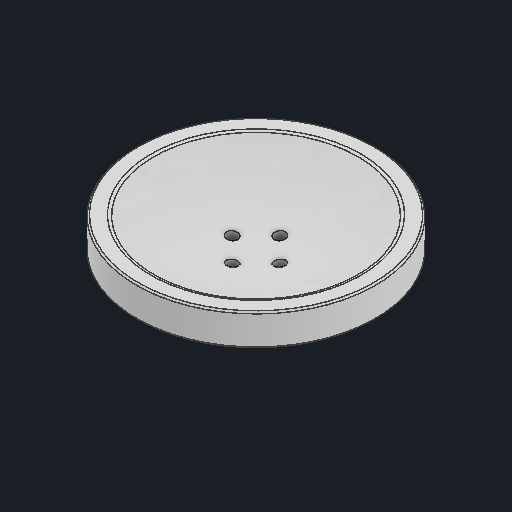
# Autodesk Inventor part: 접시
Saved by Autodesk Inventor 2026.3 (Build 303398000, 398)
## iProperties
Created: 2026-09-11
Part Number: 접시
Material: 일반
Document SubType Name: Modeling
Designer: khw
Density: 1 g/cm^3
Appearance: 기본값
Author: khw
Autodesk Inventor part; units mm, degrees
ref_plane "YZ Plane" through (0, 0, 0) normal (1, 0, 0) x (0, 1, 0)
ref_plane "XZ Plane" through (0, 0, 0) normal (0, 1, 0) x (-1, 0, 0)
ref_plane "XY Plane" through (0, 0, 0) normal (0, 0, 1) x (1, 0, 0)
sketch "스케치1" plane through (0, 0, 0) normal (1, 0, 0) x (0, 1, 0)
  line L0 (0, 0) -> (0, -25)
  line L1 (0, -25) -> (25, -25)
  line L2 (25, -25) -> (25, -75)
  line L3 (25, -75) -> (45, -75)
  arc A0 (25, 0) -> (45, -65) centre (140.625, 0) ccw
  line L4 (25, 0) -> (0, 0)
  line L5 (45, -75) -> (45, -65)
  point P0 (0, -12.5)
  dimension "d0" = 50
  dimension "d1" = 150
  dimension "d2" = 20
  dimension "d3" = 25
  dimension "d4" = 10
  dimension "d5" = 20
  constraints: 12 end point, 4 perpendicular, 2 point on circle, 1 centre point, 1 horizontal, 1 line through centre, 1 midpoint, 1 vertical
  measures "d0" diameter of L1 L4
  measures "d1" diameter of L3 L4
  measures "d2" distance of L3.end L2.end
  measures "d3" distance from line of point (0, -12.5) L2
  measures "d4" distance of L3.end L5.end
  measures "d5" horizontal distance of L5.end L4.start
revolve "회전1" add sketch "스케치1" angle 360 about axis through (0, 25, 0) along (0, -1, 0)
fillet "모깎기1" radius 15 1 edges at (0, 25, 25)
sketch "스케치2" plane through (0, 0, 0) normal (0, -1, 0) x (1, 0, 0)
  line L0 (0, 0) -> (0, 15) construction
  circle A0 centre (0, 0) radius 25 projected
  line L1 (0, 0) -> (-15, 0) construction
  line L2 (0, 0) -> (0, -15) construction
  line L3 (0, 0) -> (15, 0) construction
  dimension "d8" = 15
  dimension "d11" = 360
  constraints: 8 end point, 6 coincident, 1 vertical, 19 other
  measures "d8" distance of L0.start L0.end
hole "구멍1" at (0, 0, 15) at (-15, 0, 0) at (0, 0, -15) at (15, 0, 0) direction (0, 1, 0) diameter 4 end through all
sketch "스케치3" plane through (0, 45, 0) normal (0, 1, 0) x (1, 0, 0)
  circle A0 centre (0, 0) radius 65 projected
  line L0 (0, 0) -> (0, 15) construction
  circle A1 centre (0, 15) radius 3.5
  circle A2 centre (0, 15) radius 2 projected
  line L1 (0, 0) -> (-15, 0) construction
  circle A3 centre (-15, 0) radius 3.5
  line L2 (0, 0) -> (0, -15) construction
  circle A4 centre (0, -15) radius 3.5
  line L3 (0, 0) -> (15, 0) construction
  circle A5 centre (15, 0) radius 3.5
  point P0 (0, 0)
  dimension "d20" = 7
  dimension "d23" = 360
  constraints: 8 end point, 4 centre point, 4 coincident, 1 horizontal alignment, 1 vertical, 26 other
  measures "d20" diameter of A1
extrude "돌출1" cut sketch "스케치3" against normal blind 35 contours A1 | A2 | A3 | A4 | A5
chamfer "모따기1" distance 1 angle 45 4 edges at (0, 0, 25) (0, 25, 75) (0, 45, 75) (0, 45, 65)
